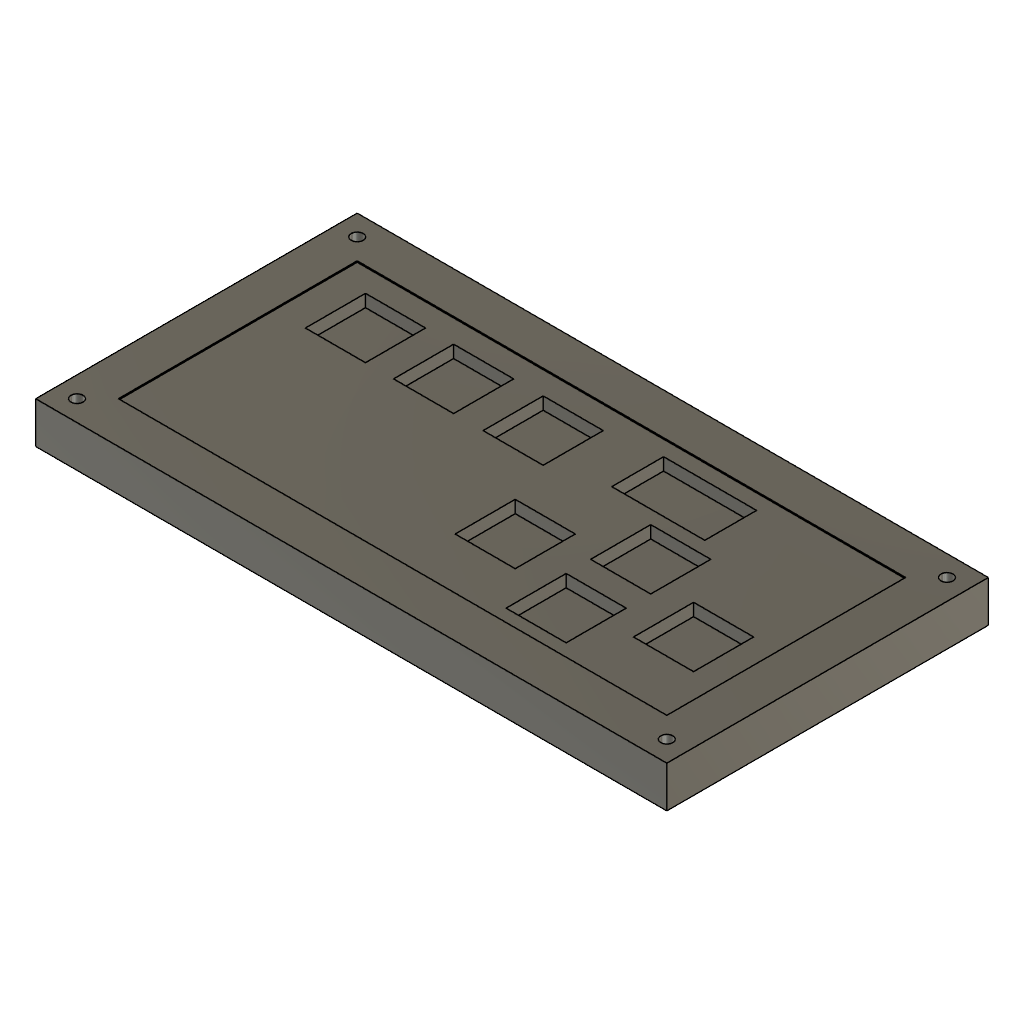
Hackpad (Autodesk Fusion 360 design; units mm, degrees)
part number: 2026-11-06-01-20-00-097
Autodesk Fusion 360 part; units mm, degrees
sketch "Sketch1" plane through (0, 0, 0) normal (0, 0, 1) x (1, 0, 0)
  line L0 (0, 0) -> (132.4, 0)
  line L1 (132.4, 0) -> (132.4, -57.65)
  line L2 (132.4, -57.65) -> (0, -57.65)
  line L3 (0, -57.65) -> (0, 0)
  line L4 (-10, 10) -> (142.4, 10)
  line L5 (142.4, 10) -> (142.4, -67.65)
  line L6 (142.4, -67.65) -> (-10, -67.65)
  line L7 (-10, -67.65) -> (-10, 10)
  circle A0 centre (137.4, 5) radius 1.45
  circle A1 centre (137.4, -62.65) radius 1.45
  circle A2 centre (-5, 5) radius 1.45
  circle A3 centre (-5, -62.65) radius 1.45
  dimension "d1" = 132.4
  dimension "d2" = 57.65
  dimension "d3" = 152.4
  dimension "d4" = 77.65
  dimension "d5" = 10
  dimension "d6" = 10
  dimension "d7" = 2.9
  dimension "d8" = 2.9
  dimension "d9" = 2.9
  dimension "d10" = 2.9
  dimension "d11" = 5
  dimension "d12" = 5
  dimension "d13" = 5
  dimension "d14" = 5
  dimension "d15" = 5
  dimension "d16" = 5
  dimension "d17" = 5
  dimension "d18" = 5
  constraint horizontal L0
  constraint vertical L1
  constraint horizontal L2
  constraint vertical L3
  constraint coincident L0.start L3.end
  constraint horizontal L4
  constraint vertical L5
  constraint horizontal L6
  constraint vertical L7
  measures "d1" distance of L0.start L0.end
  measures "d2" distance of L0.start L2.end
  measures "d3" distance of L4.start L4.end
  measures "d4" distance of L4.start L6.end
  measures "d5" distance of L3 L7
  measures "d6" distance of L0 L4
  measures "d7" diameter of A0
  measures "d8" diameter of A1
  measures "d9" diameter of A2
  measures "d10" diameter of A3
  measures "d11" distance of L4 A2.centre
  measures "d12" distance of L7 A2.centre
  measures "d13" distance of L4 A0.centre
  measures "d14" distance of L5 A0.centre
  measures "d15" distance of L5 A1.centre
  measures "d16" distance of L6 A1.centre
  measures "d17" distance of L7 A3.centre
  measures "d18" distance of L6 A3.centre
extrude "Extrude1" add sketch "Sketch1" along normal blind 3 contours L0 L1 L2 L3 makes body 1
extrude "Extrude2" add sketch "Sketch1" along normal blind 10 bodies 1
sketch "Sketch4" plane through (0, 0, 0) normal (0, 0, 1) x (1, 0, 0)
  line L0 (-2.1278, 1.8517) -> (133.6554, 1.8517) construction
  line L1 (133.6554, 1.8517) -> (133.6554, -59.4383) construction
  line L2 (133.6554, -59.4383) -> (-2.1278, -59.4383) construction
  line L3 (-2.1278, -59.4383) -> (-2.1278, 1.8517) construction
  line L4 (-3.3818, 1.8517) -> (133.6554, 1.8517) construction
  line L5 (133.6554, 1.8517) -> (133.6554, -59.4383) construction
  line L6 (133.6554, -59.4383) -> (-3.3818, -59.4383) construction
  line L7 (-3.3818, -59.4383) -> (-3.3818, 1.8517) construction
  line L8 (-0.3685, 1.0116) -> (132.6315, 1.0116)
  line L9 (132.6315, 1.0116) -> (132.6315, -57.9884)
  line L10 (132.6315, -57.9884) -> (-0.3685, -57.9884)
  line L11 (-0.3685, -57.9884) -> (-0.3685, 1.0116)
  dimension "d31" = 133
  dimension "d32" = 59
  constraint horizontal L0
  constraint vertical L1
  constraint horizontal L2
  constraint vertical L3
  constraint horizontal L4
  constraint vertical L5
  constraint horizontal L6
  constraint vertical L7
  constraint horizontal L8
  constraint vertical L9
  constraint horizontal L10
  constraint vertical L11
  measures "d31" distance of L8.start L8.end
  measures "d32" distance of L8.start L10.end
move_face "MoveFace1" by (0, -4.5389, 5.6949) 1 faces at (44.1333, -19.2167, 3) on bodies 1
move_face "MoveFace2" by (0, -0.1671, -0.7797) 1 faces at (44.1333, -19.2167, 8.6949) on bodies 1
move_face "MoveFace3" by (0, -8.3487, 1.2921) 1 faces at (44.1333, -19.2167, 7.9152) on bodies 1
delete_face "DeleteFace1" 1 faces at (44.1333, -19.2167, 9.2072) on bodies 1
extrude "Extrude3" add sketch "Sketch4" sketch "Sketch1" along normal blind 3 separate body of sketch 2 contours L0 L1 L2 L3 makes body 2
move_face "MoveFace4" by (0, -3.8004, 5.7059) 1 faces at (43.9648, -38.3218, 3) on bodies 2
extrude "Extrude4" add 1 faces at (43.9648, -38.3218, 8.7059) along direction (0, 0, 1) blind 1 on bodies 2 bodies 1 2
sketch "Sketch5" plane through (-10, 0, 0) normal (-1, 0, 0) x (0, -1, 0)
  line L0 (67.65, 10) -> (-10, 10)
  line L1 (-10, 10) -> (-10, 0)
  line L2 (-10, 0) -> (67.65, 0)
  line L3 (67.65, 0) -> (67.65, 10)
  line L4 (34.2194, 6.6074) -> (49.3626, 6.6074)
  line L5 (49.3626, 6.6074) -> (49.3626, 1.9919)
  line L6 (49.3626, 1.9919) -> (34.2194, 1.9919)
  line L7 (34.2194, 1.9919) -> (34.2194, 6.6074)
  constraint horizontal L4
  constraint vertical L5
  constraint horizontal L6
  constraint vertical L7
extrude "Extrude5" cut sketch "Sketch5" against normal blind 10.5 contours L4 L5 L6 L7 bodies 1
sketch "Sketch6" plane through (0, 0, 9.7059) normal (0, 0, 1) x (-1, 0, 0)
  line L0 (0, 57.65) -> (-132.4, 57.65)
  line L1 (-132.4, 57.65) -> (-132.4, 0)
  line L2 (-132.4, 0) -> (0, 0)
  line L3 (0, 0) -> (0, 57.65)
  line L4 (-7.5, 5.5) -> (-22, 5.5)
  line L5 (-22, 5.5) -> (-22, 20)
  line L6 (-22, 20) -> (-7.5, 20)
  line L7 (-7.5, 20) -> (-7.5, 5.5)
  line L8 (-28.7734, 5.5) -> (-43.2734, 5.5)
  line L9 (-43.2734, 5.5) -> (-43.2734, 20)
  line L10 (-43.2734, 20) -> (-28.7734, 20)
  line L11 (-28.7734, 20) -> (-28.7734, 5.5)
  line L12 (-50.3962, 5.5) -> (-64.8962, 5.5)
  line L13 (-64.8962, 5.5) -> (-64.8962, 20)
  line L14 (-64.8962, 20) -> (-50.3962, 20)
  line L15 (-50.3962, 20) -> (-50.3962, 5.5)
  line L16 (-68.6482, 30.4961) -> (-83.1482, 30.4961)
  line L17 (-83.1482, 30.4961) -> (-83.1482, 44.9961)
  line L18 (-83.1482, 44.9961) -> (-68.6482, 44.9961)
  line L19 (-68.6482, 44.9961) -> (-68.6482, 30.4961)
  line L20 (-111.7064, 30.4961) -> (-126.2064, 30.4961)
  line L21 (-126.2064, 30.4961) -> (-126.2064, 44.9961)
  line L22 (-126.2064, 44.9961) -> (-111.7064, 44.9961)
  line L23 (-111.7064, 44.9961) -> (-111.7064, 30.4961)
  line L24 (-90.2943, 19.43) -> (-104.7943, 19.43)
  line L25 (-104.7943, 19.43) -> (-104.7943, 33.93)
  line L26 (-104.7943, 33.93) -> (-90.2943, 33.93)
  line L27 (-90.2943, 33.93) -> (-90.2943, 19.43)
  line L28 (-90.2943, 39.849) -> (-104.7943, 39.849)
  line L29 (-104.7943, 39.849) -> (-104.7943, 54.349)
  line L30 (-104.7943, 54.349) -> (-90.2943, 54.349)
  line L31 (-90.2943, 54.349) -> (-90.2943, 39.849)
  dimension "d39" = 14.5
  dimension "d40" = 14.5
  dimension "d41" = 14.5
  dimension "d42" = 14.5
  dimension "d43" = 14.5
  dimension "d44" = 14.5
  dimension "d45" = 14.5
  dimension "d46" = 14.5
  dimension "d47" = 14.5
  dimension "d48" = 14.5
  dimension "d49" = 14.5
  dimension "d50" = 14.5
  constraint horizontal L4
  constraint vertical L5
  constraint horizontal L6
  constraint vertical L7
  constraint horizontal L8
  constraint vertical L9
  constraint horizontal L10
  constraint vertical L11
  constraint horizontal L12
  constraint vertical L13
  constraint horizontal L14
  constraint vertical L15
  constraint horizontal L16
  constraint vertical L17
  constraint horizontal L18
  constraint vertical L19
  constraint horizontal L20
  constraint vertical L21
  constraint horizontal L22
  constraint vertical L23
  constraint horizontal L24
  constraint vertical L25
  constraint horizontal L26
  constraint vertical L27
  constraint horizontal L28
  constraint vertical L29
  constraint horizontal L30
  constraint vertical L31
  measures "d39" distance of L8.start L8.end
  measures "d40" distance of L8.start L10.end
  measures "d41" distance of L12.start L12.end
  measures "d42" distance of L12.start L14.end
  measures "d43" distance of L16.start L16.end
  measures "d44" distance of L16.start L18.end
  measures "d45" distance of L20.start L20.end
  measures "d46" distance of L20.start L22.end
  measures "d47" distance of L24.start L24.end
  measures "d48" distance of L24.start L26.end
  measures "d49" distance of L28.start L28.end
  measures "d50" distance of L28.start L30.end
extrude "Extrude6" cut sketch "Sketch6" against normal blind 3 contours L4 L5 L6 L7 | L8 L9 L10 L11 | L12 L13 L14 L15 | L16 L17 L18 L19 | L20 L21 L22 L23 | L24 L25 L26 L27 | L28 L29 L30 L31 bodies 1
sketch "Sketch7" plane through (0, 0, 9.7059) normal (0, 0, 1) x (-1, 0, 0)
  line L0 (0, 57.65) -> (-132.4, 57.65)
  line L1 (-132.4, 57.65) -> (-132.4, 0)
  line L2 (-132.4, 0) -> (0, 0)
  line L3 (0, 0) -> (0, 57.65)
  line L4 (-126.2064, 30.4961) -> (-126.2064, 44.9961)
  line L5 (-126.2064, 44.9961) -> (-111.7064, 44.9961)
  line L6 (-111.7064, 44.9961) -> (-111.7064, 30.4961)
  line L7 (-111.7064, 30.4961) -> (-126.2064, 30.4961)
  line L8 (-64.8962, 5.5) -> (-64.8962, 20)
  line L9 (-64.8962, 20) -> (-50.3962, 20)
  line L10 (-50.3962, 20) -> (-50.3962, 5.5)
  line L11 (-50.3962, 5.5) -> (-64.8962, 5.5)
  line L12 (-43.2734, 5.5) -> (-43.2734, 20)
  line L13 (-43.2734, 20) -> (-28.7734, 20)
  line L14 (-28.7734, 20) -> (-28.7734, 5.5)
  line L15 (-28.7734, 5.5) -> (-43.2734, 5.5)
  line L16 (-104.7943, 19.43) -> (-104.7943, 33.93)
  line L17 (-104.7943, 33.93) -> (-90.2943, 33.93)
  line L18 (-90.2943, 33.93) -> (-90.2943, 19.43)
  line L19 (-90.2943, 19.43) -> (-104.7943, 19.43)
  line L20 (-83.1482, 30.4961) -> (-83.1482, 44.9961)
  line L21 (-83.1482, 44.9961) -> (-68.6482, 44.9961)
  line L22 (-68.6482, 44.9961) -> (-68.6482, 30.4961)
  line L23 (-68.6482, 30.4961) -> (-83.1482, 30.4961)
  line L24 (-22, 5.5) -> (-22, 20)
  line L25 (-22, 20) -> (-7.5, 20)
  line L26 (-7.5, 20) -> (-7.5, 5.5)
  line L27 (-7.5, 5.5) -> (-22, 5.5)
  line L28 (-104.7943, 39.849) -> (-104.7943, 54.349)
  line L29 (-104.7943, 54.349) -> (-90.2943, 54.349)
  line L30 (-90.2943, 54.349) -> (-90.2943, 39.849)
  line L31 (-90.2943, 39.849) -> (-104.7943, 39.849)
  line L32 (-77.6462, 3.68) -> (-100.0962, 3.68)
  line L33 (-100.0962, 3.68) -> (-100.0962, 16.18)
  line L34 (-100.0962, 16.18) -> (-77.6462, 16.18)
  line L35 (-77.6462, 16.18) -> (-77.6462, 3.68)
  dimension "d53" = 22.45
  dimension "d54" = 12.5
  dimension "d55" = 12.75
  dimension "d56" = 3.25
  constraint horizontal L32
  constraint vertical L33
  constraint horizontal L34
  constraint vertical L35
  measures "d53" distance of L32.start L32.end
  measures "d54" distance of L32.start L34.end
  measures "d55" distance of L8 L35
  measures "d56" distance of L19 L34
extrude "Extrude7" cut sketch "Sketch7" against normal blind 3 contours L32 L33 L34 L35 bodies 1
